Autodesk Fusion 360 part; units mm, degrees
(part 26 of 28)
  line L3064 (63.4347, 75.7056, -1.4859) -> (63.5097, 75.8867, -1.4859)
  line L3065 (63.5097, 75.8867, -1.4859) -> (63.6186, 76.0497, -1.4859)
  line L3066 (63.6186, 76.0497, -1.4859) -> (63.7572, 76.1883, -1.4859)
  line L3067 (63.7572, 76.1883, -1.4859) -> (63.9202, 76.2972, -1.4859)
  line L3068 (63.9202, 76.2972, -1.4859) -> (64.1013, 76.3722, -1.4859)
  line L3069 (64.1013, 76.3722, -1.4859) -> (64.2936, 76.4105, -1.4859)
  line L3070 (64.2936, 76.4105, -1.4859) -> (64.4896, 76.4105, -1.4859)
  line L3071 (64.4896, 76.4105, -1.4859) -> (64.6819, 76.3722, -1.4859)
  line L3072 (96.8769, 76.3722, -1.4859) -> (97.058, 76.2972, -1.4859)
  line L3073 (97.058, 76.2972, -1.4859) -> (97.221, 76.1883, -1.4859)
  line L3074 (97.221, 76.1883, -1.4859) -> (97.3596, 76.0497, -1.4859)
  line L3075 (97.3596, 76.0497, -1.4859) -> (97.4685, 75.8867, -1.4859)
  line L3076 (97.4685, 75.8867, -1.4859) -> (97.5435, 75.7056, -1.4859)
  line L3077 (97.5435, 75.7056, -1.4859) -> (97.5818, 75.5133, -1.4859)
  line L3078 (97.5818, 75.5133, -1.4859) -> (97.5866, 75.4153, -1.4859)
  line L3079 (97.5866, 75.4153, -1.4859) -> (97.5866, 74.2153, -1.4859)
  line L3080 (97.5866, 74.2153, -1.4859) -> (97.5818, 74.1173, -1.4859)
  line L3081 (97.5818, 74.1173, -1.4859) -> (97.5435, 73.925, -1.4859)
  line L3082 (97.5435, 73.925, -1.4859) -> (97.4685, 73.7439, -1.4859)
  line L3083 (97.4685, 73.7439, -1.4859) -> (97.3596, 73.5809, -1.4859)
  line L3084 (97.3596, 73.5809, -1.4859) -> (97.221, 73.4423, -1.4859)
  line L3085 (97.221, 73.4423, -1.4859) -> (97.058, 73.3334, -1.4859)
  line L3086 (97.058, 73.3334, -1.4859) -> (96.8769, 73.2583, -1.4859)
  line L3087 (96.8769, 73.2583, -1.4859) -> (96.6846, 73.2201, -1.4859)
  line L3088 (96.6846, 73.2201, -1.4859) -> (96.4886, 73.2201, -1.4859)
  line L3089 (96.4886, 73.2201, -1.4859) -> (96.2963, 73.2583, -1.4859)
  line L3090 (96.2963, 73.2583, -1.4859) -> (96.1152, 73.3334, -1.4859)
  line L3091 (96.1152, 73.3334, -1.4859) -> (95.9522, 73.4423, -1.4859)
  line L3092 (95.9522, 73.4423, -1.4859) -> (95.8136, 73.5809, -1.4859)
  line L3093 (95.8136, 73.5809, -1.4859) -> (95.7047, 73.7439, -1.4859)
  line L3094 (95.7047, 73.7439, -1.4859) -> (95.6297, 73.925, -1.4859)
  line L3095 (95.6297, 73.925, -1.4859) -> (95.5914, 74.1173, -1.4859)
  line L3096 (95.5914, 74.1173, -1.4859) -> (95.5866, 74.2153, -1.4859)
  line L3097 (95.5866, 74.2153, -1.4859) -> (95.5866, 75.4153, -1.4859)
  line L3098 (95.5866, 75.4153, -1.4859) -> (95.5914, 75.5133, -1.4859)
  line L3099 (95.5914, 75.5133, -1.4859) -> (95.6297, 75.7056, -1.4859)
  line L3100 (95.6297, 75.7056, -1.4859) -> (95.7047, 75.8867, -1.4859)
  line L3101 (95.7047, 75.8867, -1.4859) -> (95.8136, 76.0497, -1.4859)
  line L3102 (95.8136, 76.0497, -1.4859) -> (95.9522, 76.1883, -1.4859)
  line L3103 (95.9522, 76.1883, -1.4859) -> (96.1152, 76.2972, -1.4859)
  line L3104 (96.1152, 76.2972, -1.4859) -> (96.2963, 76.3722, -1.4859)
  line L3105 (96.2963, 76.3722, -1.4859) -> (96.4886, 76.4105, -1.4859)
  line L3106 (96.4886, 76.4105, -1.4859) -> (96.6846, 76.4105, -1.4859)
  line L3107 (96.6846, 76.4105, -1.4859) -> (96.8769, 76.3722, -1.4859)
  line L3108 (99.6069, 76.3722, -1.4859) -> (99.788, 76.2972, -1.4859)
  line L3109 (99.788, 76.2972, -1.4859) -> (99.951, 76.1883, -1.4859)
  line L3110 (99.951, 76.1883, -1.4859) -> (100.0896, 76.0497, -1.4859)
  line L3111 (100.0896, 76.0497, -1.4859) -> (100.1985, 75.8867, -1.4859)
  line L3112 (100.1985, 75.8867, -1.4859) -> (100.2735, 75.7056, -1.4859)
  line L3113 (100.2735, 75.7056, -1.4859) -> (100.3118, 75.5133, -1.4859)
  line L3114 (100.3118, 75.5133, -1.4859) -> (100.3166, 75.4153, -1.4859)
  line L3115 (100.3166, 75.4153, -1.4859) -> (100.3166, 74.2153, -1.4859)
  line L3116 (100.3166, 74.2153, -1.4859) -> (100.3118, 74.1173, -1.4859)
  line L3117 (100.3118, 74.1173, -1.4859) -> (100.2735, 73.925, -1.4859)
  line L3118 (100.2735, 73.925, -1.4859) -> (100.1985, 73.7439, -1.4859)
  line L3119 (100.1985, 73.7439, -1.4859) -> (100.0896, 73.5809, -1.4859)
  line L3120 (100.0896, 73.5809, -1.4859) -> (99.951, 73.4423, -1.4859)
  line L3121 (99.951, 73.4423, -1.4859) -> (99.788, 73.3334, -1.4859)
  line L3122 (99.788, 73.3334, -1.4859) -> (99.6069, 73.2583, -1.4859)
  line L3123 (99.6069, 73.2583, -1.4859) -> (99.4146, 73.2201, -1.4859)
  line L3124 (99.4146, 73.2201, -1.4859) -> (99.2186, 73.2201, -1.4859)
  line L3125 (99.2186, 73.2201, -1.4859) -> (99.0263, 73.2583, -1.4859)
  line L3126 (99.0263, 73.2583, -1.4859) -> (98.8452, 73.3334, -1.4859)
  line L3127 (98.8452, 73.3334, -1.4859) -> (98.6822, 73.4423, -1.4859)
  line L3128 (98.6822, 73.4423, -1.4859) -> (98.5436, 73.5809, -1.4859)
  line L3129 (98.5436, 73.5809, -1.4859) -> (98.4347, 73.7439, -1.4859)
  line L3130 (98.4347, 73.7439, -1.4859) -> (98.3597, 73.925, -1.4859)
  line L3131 (98.3597, 73.925, -1.4859) -> (98.3214, 74.1173, -1.4859)
  line L3132 (98.3214, 74.1173, -1.4859) -> (98.3166, 74.2153, -1.4859)
  line L3133 (98.3166, 74.2153, -1.4859) -> (98.3166, 75.4153, -1.4859)
  line L3134 (98.3166, 75.4153, -1.4859) -> (98.3214, 75.5133, -1.4859)
  line L3135 (98.3214, 75.5133, -1.4859) -> (98.3597, 75.7056, -1.4859)
  line L3136 (98.3597, 75.7056, -1.4859) -> (98.4347, 75.8867, -1.4859)
  line L3137 (98.4347, 75.8867, -1.4859) -> (98.5436, 76.0497, -1.4859)
  line L3138 (98.5436, 76.0497, -1.4859) -> (98.6822, 76.1883, -1.4859)
  line L3139 (98.6822, 76.1883, -1.4859) -> (98.8452, 76.2972, -1.4859)
  line L3140 (98.8452, 76.2972, -1.4859) -> (99.0263, 76.3722, -1.4859)
  line L3141 (99.0263, 76.3722, -1.4859) -> (99.2186, 76.4105, -1.4859)
  line L3142 (99.2186, 76.4105, -1.4859) -> (99.4146, 76.4105, -1.4859)
  line L3143 (99.4146, 76.4105, -1.4859) -> (99.6069, 76.3722, -1.4859)
  line L3144 (131.8019, 76.3722, -1.4859) -> (131.983, 76.2972, -1.4859)
  line L3145 (131.983, 76.2972, -1.4859) -> (132.146, 76.1883, -1.4859)
  line L3146 (132.146, 76.1883, -1.4859) -> (132.2846, 76.0497, -1.4859)
  line L3147 (132.2846, 76.0497, -1.4859) -> (132.3935, 75.8867, -1.4859)
  line L3148 (132.3935, 75.8867, -1.4859) -> (132.4685, 75.7056, -1.4859)
  line L3149 (132.4685, 75.7056, -1.4859) -> (132.5068, 75.5133, -1.4859)
  line L3150 (132.5068, 75.5133, -1.4859) -> (132.5116, 75.4153, -1.4859)
  line L3151 (132.5116, 75.4153, -1.4859) -> (132.5116, 74.2153, -1.4859)
  line L3152 (132.5116, 74.2153, -1.4859) -> (132.5068, 74.1173, -1.4859)
  line L3153 (132.5068, 74.1173, -1.4859) -> (132.4685, 73.925, -1.4859)
  line L3154 (132.4685, 73.925, -1.4859) -> (132.3935, 73.7439, -1.4859)
  line L3155 (132.3935, 73.7439, -1.4859) -> (132.2846, 73.5809, -1.4859)
  line L3156 (132.2846, 73.5809, -1.4859) -> (132.146, 73.4423, -1.4859)
  line L3157 (132.146, 73.4423, -1.4859) -> (131.983, 73.3334, -1.4859)
  line L3158 (131.983, 73.3334, -1.4859) -> (131.8019, 73.2583, -1.4859)
  line L3159 (131.8019, 73.2583, -1.4859) -> (131.6096, 73.2201, -1.4859)
  line L3160 (131.6096, 73.2201, -1.4859) -> (131.4136, 73.2201, -1.4859)
  line L3161 (131.4136, 73.2201, -1.4859) -> (131.2213, 73.2583, -1.4859)
  line L3162 (131.2213, 73.2583, -1.4859) -> (131.0402, 73.3334, -1.4859)
  line L3163 (131.0402, 73.3334, -1.4859) -> (130.8772, 73.4423, -1.4859)
  line L3164 (130.8772, 73.4423, -1.4859) -> (130.7386, 73.5809, -1.4859)
  line L3165 (130.7386, 73.5809, -1.4859) -> (130.6297, 73.7439, -1.4859)
  line L3166 (130.6297, 73.7439, -1.4859) -> (130.5547, 73.925, -1.4859)
  line L3167 (130.5547, 73.925, -1.4859) -> (130.5164, 74.1173, -1.4859)
  line L3168 (130.5164, 74.1173, -1.4859) -> (130.5116, 74.2153, -1.4859)
  line L3169 (130.5116, 74.2153, -1.4859) -> (130.5116, 75.4153, -1.4859)
  line L3170 (130.5116, 75.4153, -1.4859) -> (130.5164, 75.5133, -1.4859)
  line L3171 (130.5164, 75.5133, -1.4859) -> (130.5547, 75.7056, -1.4859)
  line L3172 (130.5547, 75.7056, -1.4859) -> (130.6297, 75.8867, -1.4859)
  line L3173 (130.6297, 75.8867, -1.4859) -> (130.7386, 76.0497, -1.4859)
  line L3174 (130.7386, 76.0497, -1.4859) -> (130.8772, 76.1883, -1.4859)
  line L3175 (130.8772, 76.1883, -1.4859) -> (131.0402, 76.2972, -1.4859)
  line L3176 (131.0402, 76.2972, -1.4859) -> (131.2213, 76.3722, -1.4859)
  line L3177 (131.2213, 76.3722, -1.4859) -> (131.4136, 76.4105, -1.4859)
  line L3178 (131.4136, 76.4105, -1.4859) -> (131.6096, 76.4105, -1.4859)
  line L3179 (131.6096, 76.4105, -1.4859) -> (131.8019, 76.3722, -1.4859)
  line L3180 (134.5319, 76.3722, -1.4859) -> (134.713, 76.2972, -1.4859)
  line L3181 (134.713, 76.2972, -1.4859) -> (134.876, 76.1883, -1.4859)
  line L3182 (134.876, 76.1883, -1.4859) -> (135.0146, 76.0497, -1.4859)
  line L3183 (135.0146, 76.0497, -1.4859) -> (135.1235, 75.8867, -1.4859)
  line L3184 (135.1235, 75.8867, -1.4859) -> (135.1985, 75.7056, -1.4859)
  line L3185 (135.1985, 75.7056, -1.4859) -> (135.2368, 75.5133, -1.4859)
  line L3186 (135.2368, 75.5133, -1.4859) -> (135.2416, 75.4153, -1.4859)
  line L3187 (135.2416, 75.4153, -1.4859) -> (135.2416, 74.2153, -1.4859)
  line L3188 (135.2416, 74.2153, -1.4859) -> (135.2368, 74.1173, -1.4859)
  line L3189 (135.2368, 74.1173, -1.4859) -> (135.1985, 73.925, -1.4859)
  line L3190 (135.1985, 73.925, -1.4859) -> (135.1235, 73.7439, -1.4859)
  line L3191 (135.1235, 73.7439, -1.4859) -> (135.0146, 73.5809, -1.4859)
  line L3192 (135.0146, 73.5809, -1.4859) -> (134.876, 73.4423, -1.4859)
  line L3193 (134.876, 73.4423, -1.4859) -> (134.713, 73.3334, -1.4859)
  line L3194 (134.713, 73.3334, -1.4859) -> (134.5319, 73.2583, -1.4859)
  line L3195 (134.5319, 73.2583, -1.4859) -> (134.3396, 73.2201, -1.4859)
  line L3196 (134.3396, 73.2201, -1.4859) -> (134.1436, 73.2201, -1.4859)
  line L3197 (134.1436, 73.2201, -1.4859) -> (133.9513, 73.2583, -1.4859)
  line L3198 (133.9513, 73.2583, -1.4859) -> (133.7702, 73.3334, -1.4859)
  line L3199 (133.7702, 73.3334, -1.4859) -> (133.6072, 73.4423, -1.4859)
  line L3200 (133.6072, 73.4423, -1.4859) -> (133.4686, 73.5809, -1.4859)
  line L3201 (133.4686, 73.5809, -1.4859) -> (133.3597, 73.7439, -1.4859)
  line L3202 (133.3597, 73.7439, -1.4859) -> (133.2847, 73.925, -1.4859)
  line L3203 (133.2847, 73.925, -1.4859) -> (133.2464, 74.1173, -1.4859)
  line L3204 (133.2464, 74.1173, -1.4859) -> (133.2416, 74.2153, -1.4859)
  line L3205 (133.2416, 74.2153, -1.4859) -> (133.2416, 75.4153, -1.4859)
  line L3206 (133.2416, 75.4153, -1.4859) -> (133.2464, 75.5133, -1.4859)
  line L3207 (133.2464, 75.5133, -1.4859) -> (133.2847, 75.7056, -1.4859)
  line L3208 (133.2847, 75.7056, -1.4859) -> (133.3597, 75.8867, -1.4859)
  line L3209 (133.3597, 75.8867, -1.4859) -> (133.4686, 76.0497, -1.4859)
  line L3210 (133.4686, 76.0497, -1.4859) -> (133.6072, 76.1883, -1.4859)
  line L3211 (133.6072, 76.1883, -1.4859) -> (133.7702, 76.2972, -1.4859)
  line L3212 (133.7702, 76.2972, -1.4859) -> (133.9513, 76.3722, -1.4859)
  line L3213 (133.9513, 76.3722, -1.4859) -> (134.1436, 76.4105, -1.4859)
  line L3214 (134.1436, 76.4105, -1.4859) -> (134.3396, 76.4105, -1.4859)
  line L3215 (134.3396, 76.4105, -1.4859) -> (134.5319, 76.3722, -1.4859)
  line L3216 (14.4315, 73.2735, -1.4859) -> (12.4315, 73.2735, -1.4859)
  line L3217 (12.4315, 73.2735, -1.4859) -> (12.4315, 76.4735, -1.4859)
  line L3218 (12.4315, 76.4735, -1.4859) -> (14.4315, 76.4735, -1.4859)
  line L3219 (14.4315, 76.4735, -1.4859) -> (14.4315, 73.2735, -1.4859)
  line L3220 (49.3565, 73.2735, -1.4859) -> (47.3565, 73.2735, -1.4859)
  line L3221 (47.3565, 73.2735, -1.4859) -> (47.3565, 76.4735, -1.4859)
  line L3222 (47.3565, 76.4735, -1.4859) -> (49.3565, 76.4735, -1.4859)
  line L3223 (49.3565, 76.4735, -1.4859) -> (49.3565, 73.2735, -1.4859)
  line L3224 (84.2815, 73.2735, -1.4859) -> (82.2815, 73.2735, -1.4859)
  line L3225 (82.2815, 73.2735, -1.4859) -> (82.2815, 76.4735, -1.4859)
  line L3226 (82.2815, 76.4735, -1.4859) -> (84.2815, 76.4735, -1.4859)
  line L3227 (84.2815, 76.4735, -1.4859) -> (84.2815, 73.2735, -1.4859)
  line L3228 (119.2065, 73.2735, -1.4859) -> (117.2065, 73.2735, -1.4859)
  line L3229 (117.2065, 73.2735, -1.4859) -> (117.2065, 76.4735, -1.4859)
  line L3230 (117.2065, 76.4735, -1.4859) -> (119.2065, 76.4735, -1.4859)
  line L3231 (119.2065, 76.4735, -1.4859) -> (119.2065, 73.2735, -1.4859)
  line L3232 (16.4918, 76.4304, -1.4859) -> (16.6729, 76.3554, -1.4859)
  line L3233 (16.6729, 76.3554, -1.4859) -> (16.8359, 76.2465, -1.4859)
  line L3234 (16.8359, 76.2465, -1.4859) -> (16.9745, 76.1079, -1.4859)
  line L3235 (16.9745, 76.1079, -1.4859) -> (17.0834, 75.9449, -1.4859)
  line L3236 (17.0834, 75.9449, -1.4859) -> (17.1585, 75.7638, -1.4859)
  line L3237 (17.1585, 75.7638, -1.4859) -> (17.1967, 75.5715, -1.4859)
  line L3238 (17.1967, 75.5715, -1.4859) -> (17.2015, 75.4735, -1.4859)
  line L3239 (17.2015, 75.4735, -1.4859) -> (17.2015, 74.2735, -1.4859)
  line L3240 (17.2015, 74.2735, -1.4859) -> (17.1967, 74.1755, -1.4859)
  line L3241 (17.1967, 74.1755, -1.4859) -> (17.1585, 73.9832, -1.4859)
  line L3242 (17.1585, 73.9832, -1.4859) -> (17.0834, 73.8021, -1.4859)
  line L3243 (17.0834, 73.8021, -1.4859) -> (16.9745, 73.6391, -1.4859)
  line L3244 (16.9745, 73.6391, -1.4859) -> (16.8359, 73.5005, -1.4859)
  line L3245 (16.8359, 73.5005, -1.4859) -> (16.6729, 73.3916, -1.4859)
  line L3246 (16.6729, 73.3916, -1.4859) -> (16.4918, 73.3165, -1.4859)
  line L3247 (16.4918, 73.3165, -1.4859) -> (16.2995, 73.2783, -1.4859)
  line L3248 (16.2995, 73.2783, -1.4859) -> (16.1035, 73.2783, -1.4859)
  line L3249 (16.1035, 73.2783, -1.4859) -> (15.9112, 73.3165, -1.4859)
  line L3250 (15.9112, 73.3165, -1.4859) -> (15.7301, 73.3916, -1.4859)
  line L3251 (15.7301, 73.3916, -1.4859) -> (15.5671, 73.5005, -1.4859)
  line L3252 (15.5671, 73.5005, -1.4859) -> (15.4285, 73.6391, -1.4859)
  line L3253 (15.4285, 73.6391, -1.4859) -> (15.3196, 73.8021, -1.4859)
  line L3254 (15.3196, 73.8021, -1.4859) -> (15.2446, 73.9832, -1.4859)
  line L3255 (15.2446, 73.9832, -1.4859) -> (15.2063, 74.1755, -1.4859)
  line L3256 (15.2063, 74.1755, -1.4859) -> (15.2015, 74.2735, -1.4859)
  line L3257 (15.2015, 74.2735, -1.4859) -> (15.2015, 75.4735, -1.4859)
  line L3258 (15.2015, 75.4735, -1.4859) -> (15.2063, 75.5715, -1.4859)
  line L3259 (15.2063, 75.5715, -1.4859) -> (15.2446, 75.7638, -1.4859)
  line L3260 (15.2446, 75.7638, -1.4859) -> (15.3196, 75.9449, -1.4859)
  line L3261 (15.3196, 75.9449, -1.4859) -> (15.4285, 76.1079, -1.4859)
  line L3262 (15.4285, 76.1079, -1.4859) -> (15.5671, 76.2465, -1.4859)
  line L3263 (15.5671, 76.2465, -1.4859) -> (15.7301, 76.3554, -1.4859)
  line L3264 (15.7301, 76.3554, -1.4859) -> (15.9112, 76.4304, -1.4859)
  line L3265 (15.9112, 76.4304, -1.4859) -> (16.1035, 76.4687, -1.4859)
  line L3266 (16.1035, 76.4687, -1.4859) -> (16.2995, 76.4687, -1.4859)
  line L3267 (16.2995, 76.4687, -1.4859) -> (16.4918, 76.4304, -1.4859)
  line L3268 (19.2218, 76.4304, -1.4859) -> (19.4029, 76.3554, -1.4859)
  line L3269 (19.4029, 76.3554, -1.4859) -> (19.5659, 76.2465, -1.4859)
  line L3270 (19.5659, 76.2465, -1.4859) -> (19.7045, 76.1079, -1.4859)
  line L3271 (19.7045, 76.1079, -1.4859) -> (19.8134, 75.9449, -1.4859)
  line L3272 (19.8134, 75.9449, -1.4859) -> (19.8885, 75.7638, -1.4859)
  line L3273 (19.8885, 75.7638, -1.4859) -> (19.9267, 75.5715, -1.4859)
  line L3274 (19.9267, 75.5715, -1.4859) -> (19.9315, 75.4735, -1.4859)
  line L3275 (19.9315, 75.4735, -1.4859) -> (19.9315, 74.2735, -1.4859)
  line L3276 (19.9315, 74.2735, -1.4859) -> (19.9267, 74.1755, -1.4859)
  line L3277 (19.9267, 74.1755, -1.4859) -> (19.8885, 73.9832, -1.4859)
  line L3278 (19.8885, 73.9832, -1.4859) -> (19.8134, 73.8021, -1.4859)
  line L3279 (19.8134, 73.8021, -1.4859) -> (19.7045, 73.6391, -1.4859)
  line L3280 (19.7045, 73.6391, -1.4859) -> (19.5659, 73.5005, -1.4859)
  line L3281 (19.5659, 73.5005, -1.4859) -> (19.4029, 73.3916, -1.4859)
  line L3282 (19.4029, 73.3916, -1.4859) -> (19.2218, 73.3165, -1.4859)
  line L3283 (19.2218, 73.3165, -1.4859) -> (19.0295, 73.2783, -1.4859)
  line L3284 (19.0295, 73.2783, -1.4859) -> (18.8335, 73.2783, -1.4859)
  line L3285 (18.8335, 73.2783, -1.4859) -> (18.6412, 73.3165, -1.4859)
  line L3286 (18.6412, 73.3165, -1.4859) -> (18.4601, 73.3916, -1.4859)
  line L3287 (18.4601, 73.3916, -1.4859) -> (18.2971, 73.5005, -1.4859)
  line L3288 (18.2971, 73.5005, -1.4859) -> (18.1585, 73.6391, -1.4859)
  line L3289 (18.1585, 73.6391, -1.4859) -> (18.0496, 73.8021, -1.4859)
  line L3290 (18.0496, 73.8021, -1.4859) -> (17.9746, 73.9832, -1.4859)
  line L3291 (17.9746, 73.9832, -1.4859) -> (17.9363, 74.1755, -1.4859)
  line L3292 (17.9363, 74.1755, -1.4859) -> (17.9315, 74.2735, -1.4859)
  line L3293 (17.9315, 74.2735, -1.4859) -> (17.9315, 75.4735, -1.4859)
  line L3294 (17.9315, 75.4735, -1.4859) -> (17.9363, 75.5715, -1.4859)
  line L3295 (17.9363, 75.5715, -1.4859) -> (17.9746, 75.7638, -1.4859)
  line L3296 (17.9746, 75.7638, -1.4859) -> (18.0496, 75.9449, -1.4859)
  line L3297 (18.0496, 75.9449, -1.4859) -> (18.1585, 76.1079, -1.4859)
  line L3298 (18.1585, 76.1079, -1.4859) -> (18.2971, 76.2465, -1.4859)
  line L3299 (18.2971, 76.2465, -1.4859) -> (18.4601, 76.3554, -1.4859)
  line L3300 (18.4601, 76.3554, -1.4859) -> (18.6412, 76.4304, -1.4859)
  line L3301 (18.6412, 76.4304, -1.4859) -> (18.8335, 76.4687, -1.4859)
  line L3302 (18.8335, 76.4687, -1.4859) -> (19.0295, 76.4687, -1.4859)
  line L3303 (19.0295, 76.4687, -1.4859) -> (19.2218, 76.4304, -1.4859)
  line L3304 (51.4168, 76.4304, -1.4859) -> (51.5979, 76.3554, -1.4859)
  line L3305 (51.5979, 76.3554, -1.4859) -> (51.7609, 76.2465, -1.4859)
  line L3306 (51.7609, 76.2465, -1.4859) -> (51.8995, 76.1079, -1.4859)
  line L3307 (51.8995, 76.1079, -1.4859) -> (52.0084, 75.9449, -1.4859)
  line L3308 (52.0084, 75.9449, -1.4859) -> (52.0835, 75.7638, -1.4859)
  line L3309 (52.0835, 75.7638, -1.4859) -> (52.1217, 75.5715, -1.4859)
  line L3310 (52.1217, 75.5715, -1.4859) -> (52.1265, 75.4735, -1.4859)
  line L3311 (52.1265, 75.4735, -1.4859) -> (52.1265, 74.2735, -1.4859)
  line L3312 (52.1265, 74.2735, -1.4859) -> (52.1217, 74.1755, -1.4859)
  line L3313 (52.1217, 74.1755, -1.4859) -> (52.0835, 73.9832, -1.4859)
  line L3314 (52.0835, 73.9832, -1.4859) -> (52.0084, 73.8021, -1.4859)
  line L3315 (52.0084, 73.8021, -1.4859) -> (51.8995, 73.6391, -1.4859)
  line L3316 (51.8995, 73.6391, -1.4859) -> (51.7609, 73.5005, -1.4859)
  line L3317 (51.7609, 73.5005, -1.4859) -> (51.5979, 73.3916, -1.4859)
  line L3318 (51.5979, 73.3916, -1.4859) -> (51.4168, 73.3165, -1.4859)
  line L3319 (51.4168, 73.3165, -1.4859) -> (51.2245, 73.2783, -1.4859)
  line L3320 (51.2245, 73.2783, -1.4859) -> (51.0285, 73.2783, -1.4859)
  line L3321 (51.0285, 73.2783, -1.4859) -> (50.8362, 73.3165, -1.4859)
  line L3322 (50.8362, 73.3165, -1.4859) -> (50.6551, 73.3916, -1.4859)
  line L3323 (50.6551, 73.3916, -1.4859) -> (50.4921, 73.5005, -1.4859)
  line L3324 (50.4921, 73.5005, -1.4859) -> (50.3535, 73.6391, -1.4859)
  line L3325 (50.3535, 73.6391, -1.4859) -> (50.2446, 73.8021, -1.4859)
  line L3326 (50.2446, 73.8021, -1.4859) -> (50.1696, 73.9832, -1.4859)
  line L3327 (50.1696, 73.9832, -1.4859) -> (50.1313, 74.1755, -1.4859)
  line L3328 (50.1313, 74.1755, -1.4859) -> (50.1265, 74.2735, -1.4859)
  line L3329 (50.1265, 74.2735, -1.4859) -> (50.1265, 75.4735, -1.4859)
  line L3330 (50.1265, 75.4735, -1.4859) -> (50.1313, 75.5715, -1.4859)
  line L3331 (50.1313, 75.5715, -1.4859) -> (50.1696, 75.7638, -1.4859)
  line L3332 (50.1696, 75.7638, -1.4859) -> (50.2446, 75.9449, -1.4859)
  line L3333 (50.2446, 75.9449, -1.4859) -> (50.3535, 76.1079, -1.4859)
  line L3334 (50.3535, 76.1079, -1.4859) -> (50.4921, 76.2465, -1.4859)
  line L3335 (50.4921, 76.2465, -1.4859) -> (50.6551, 76.3554, -1.4859)
  line L3336 (50.6551, 76.3554, -1.4859) -> (50.8362, 76.4304, -1.4859)
  line L3337 (50.8362, 76.4304, -1.4859) -> (51.0285, 76.4687, -1.4859)
  line L3338 (51.0285, 76.4687, -1.4859) -> (51.2245, 76.4687, -1.4859)
  line L3339 (51.2245, 76.4687, -1.4859) -> (51.4168, 76.4304, -1.4859)
  line L3340 (54.1468, 76.4304, -1.4859) -> (54.3279, 76.3554, -1.4859)
  line L3341 (54.3279, 76.3554, -1.4859) -> (54.4909, 76.2465, -1.4859)
  line L3342 (54.4909, 76.2465, -1.4859) -> (54.6295, 76.1079, -1.4859)
  line L3343 (54.6295, 76.1079, -1.4859) -> (54.7384, 75.9449, -1.4859)
  line L3344 (54.7384, 75.9449, -1.4859) -> (54.8135, 75.7638, -1.4859)
  line L3345 (54.8135, 75.7638, -1.4859) -> (54.8517, 75.5715, -1.4859)
  line L3346 (54.8517, 75.5715, -1.4859) -> (54.8565, 75.4735, -1.4859)
  line L3347 (54.8565, 75.4735, -1.4859) -> (54.8565, 74.2735, -1.4859)
  line L3348 (54.8565, 74.2735, -1.4859) -> (54.8517, 74.1755, -1.4859)
  line L3349 (54.8517, 74.1755, -1.4859) -> (54.8135, 73.9832, -1.4859)
  line L3350 (54.8135, 73.9832, -1.4859) -> (54.7384, 73.8021, -1.4859)
  line L3351 (54.7384, 73.8021, -1.4859) -> (54.6295, 73.6391, -1.4859)
  line L3352 (54.6295, 73.6391, -1.4859) -> (54.4909, 73.5005, -1.4859)
  line L3353 (54.4909, 73.5005, -1.4859) -> (54.3279, 73.3916, -1.4859)
  line L3354 (54.3279, 73.3916, -1.4859) -> (54.1468, 73.3165, -1.4859)
  line L3355 (54.1468, 73.3165, -1.4859) -> (53.9545, 73.2783, -1.4859)
  line L3356 (53.9545, 73.2783, -1.4859) -> (53.7585, 73.2783, -1.4859)
  line L3357 (53.7585, 73.2783, -1.4859) -> (53.5662, 73.3165, -1.4859)
  line L3358 (53.5662, 73.3165, -1.4859) -> (53.3851, 73.3916, -1.4859)
  line L3359 (53.3851, 73.3916, -1.4859) -> (53.2221, 73.5005, -1.4859)
  line L3360 (53.2221, 73.5005, -1.4859) -> (53.0835, 73.6391, -1.4859)
  line L3361 (53.0835, 73.6391, -1.4859) -> (52.9746, 73.8021, -1.4859)
  line L3362 (52.9746, 73.8021, -1.4859) -> (52.8996, 73.9832, -1.4859)
  line L3363 (52.8996, 73.9832, -1.4859) -> (52.8613, 74.1755, -1.4859)
  line L3364 (52.8613, 74.1755, -1.4859) -> (52.8565, 74.2735, -1.4859)
  line L3365 (52.8565, 74.2735, -1.4859) -> (52.8565, 75.4735, -1.4859)
  line L3366 (52.8565, 75.4735, -1.4859) -> (52.8613, 75.5715, -1.4859)
  line L3367 (52.8613, 75.5715, -1.4859) -> (52.8996, 75.7638, -1.4859)
  line L3368 (52.8996, 75.7638, -1.4859) -> (52.9746, 75.9449, -1.4859)
  line L3369 (52.9746, 75.9449, -1.4859) -> (53.0835, 76.1079, -1.4859)
  line L3370 (53.0835, 76.1079, -1.4859) -> (53.2221, 76.2465, -1.4859)
  line L3371 (53.2221, 76.2465, -1.4859) -> (53.3851, 76.3554, -1.4859)
  line L3372 (53.3851, 76.3554, -1.4859) -> (53.5662, 76.4304, -1.4859)
  line L3373 (53.5662, 76.4304, -1.4859) -> (53.7585, 76.4687, -1.4859)
  line L3374 (53.7585, 76.4687, -1.4859) -> (53.9545, 76.4687, -1.4859)
  line L3375 (53.9545, 76.4687, -1.4859) -> (54.1468, 76.4304, -1.4859)
  line L3376 (86.3418, 76.4304, -1.4859) -> (86.5229, 76.3554, -1.4859)
  line L3377 (86.5229, 76.3554, -1.4859) -> (86.6859, 76.2465, -1.4859)
  line L3378 (86.6859, 76.2465, -1.4859) -> (86.8245, 76.1079, -1.4859)
  line L3379 (86.8245, 76.1079, -1.4859) -> (86.9334, 75.9449, -1.4859)
  line L3380 (86.9334, 75.9449, -1.4859) -> (87.0085, 75.7638, -1.4859)
  line L3381 (87.0085, 75.7638, -1.4859) -> (87.0467, 75.5715, -1.4859)
  line L3382 (87.0467, 75.5715, -1.4859) -> (87.0515, 75.4735, -1.4859)
  line L3383 (87.0515, 75.4735, -1.4859) -> (87.0515, 74.2735, -1.4859)
  line L3384 (87.0515, 74.2735, -1.4859) -> (87.0467, 74.1755, -1.4859)
  line L3385 (87.0467, 74.1755, -1.4859) -> (87.0085, 73.9832, -1.4859)
  line L3386 (87.0085, 73.9832, -1.4859) -> (86.9334, 73.8021, -1.4859)
  line L3387 (86.9334, 73.8021, -1.4859) -> (86.8245, 73.6391, -1.4859)
  line L3388 (86.8245, 73.6391, -1.4859) -> (86.6859, 73.5005, -1.4859)
  line L3389 (86.6859, 73.5005, -1.4859) -> (86.5229, 73.3916, -1.4859)
  line L3390 (86.5229, 73.3916, -1.4859) -> (86.3418, 73.3165, -1.4859)
  line L3391 (86.3418, 73.3165, -1.4859) -> (86.1495, 73.2783, -1.4859)
  line L3392 (86.1495, 73.2783, -1.4859) -> (85.9535, 73.2783, -1.4859)
  line L3393 (85.9535, 73.2783, -1.4859) -> (85.7612, 73.3165, -1.4859)
  line L3394 (85.7612, 73.3165, -1.4859) -> (85.5801, 73.3916, -1.4859)
  line L3395 (85.5801, 73.3916, -1.4859) -> (85.4171, 73.5005, -1.4859)
  line L3396 (85.4171, 73.5005, -1.4859) -> (85.2785, 73.6391, -1.4859)
  line L3397 (85.2785, 73.6391, -1.4859) -> (85.1696, 73.8021, -1.4859)
  line L3398 (85.1696, 73.8021, -1.4859) -> (85.0946, 73.9832, -1.4859)
  line L3399 (85.0946, 73.9832, -1.4859) -> (85.0563, 74.1755, -1.4859)
  line L3400 (85.0563, 74.1755, -1.4859) -> (85.0515, 74.2735, -1.4859)
  line L3401 (85.0515, 74.2735, -1.4859) -> (85.0515, 75.4735, -1.4859)
  line L3402 (85.0515, 75.4735, -1.4859) -> (85.0563, 75.5715, -1.4859)
  line L3403 (85.0563, 75.5715, -1.4859) -> (85.0946, 75.7638, -1.4859)
  line L3404 (85.0946, 75.7638, -1.4859) -> (85.1696, 75.9449, -1.4859)
  line L3405 (85.1696, 75.9449, -1.4859) -> (85.2785, 76.1079, -1.4859)
  line L3406 (85.2785, 76.1079, -1.4859) -> (85.4171, 76.2465, -1.4859)
  line L3407 (85.4171, 76.2465, -1.4859) -> (85.5801, 76.3554, -1.4859)
  line L3408 (85.5801, 76.3554, -1.4859) -> (85.7612, 76.4304, -1.4859)
  line L3409 (85.7612, 76.4304, -1.4859) -> (85.9535, 76.4687, -1.4859)
  line L3410 (85.9535, 76.4687, -1.4859) -> (86.1495, 76.4687, -1.4859)
  line L3411 (86.1495, 76.4687, -1.4859) -> (86.3418, 76.4304, -1.4859)
  line L3412 (89.0718, 76.4304, -1.4859) -> (89.2529, 76.3554, -1.4859)
  line L3413 (89.2529, 76.3554, -1.4859) -> (89.4159, 76.2465, -1.4859)
  line L3414 (89.4159, 76.2465, -1.4859) -> (89.5545, 76.1079, -1.4859)
  line L3415 (89.5545, 76.1079, -1.4859) -> (89.6634, 75.9449, -1.4859)
  line L3416 (89.6634, 75.9449, -1.4859) -> (89.7385, 75.7638, -1.4859)
  line L3417 (89.7385, 75.7638, -1.4859) -> (89.7767, 75.5715, -1.4859)
  line L3418 (89.7767, 75.5715, -1.4859) -> (89.7815, 75.4735, -1.4859)
  line L3419 (89.7815, 75.4735, -1.4859) -> (89.7815, 74.2735, -1.4859)
  line L3420 (89.7815, 74.2735, -1.4859) -> (89.7767, 74.1755, -1.4859)
  line L3421 (89.7767, 74.1755, -1.4859) -> (89.7385, 73.9832, -1.4859)
  line L3422 (89.7385, 73.9832, -1.4859) -> (89.6634, 73.8021, -1.4859)
  line L3423 (89.6634, 73.8021, -1.4859) -> (89.5545, 73.6391, -1.4859)
  line L3424 (89.5545, 73.6391, -1.4859) -> (89.4159, 73.5005, -1.4859)
  line L3425 (89.4159, 73.5005, -1.4859) -> (89.2529, 73.3916, -1.4859)
  line L3426 (89.2529, 73.3916, -1.4859) -> (89.0718, 73.3165, -1.4859)
  line L3427 (89.0718, 73.3165, -1.4859) -> (88.8795, 73.2783, -1.4859)
  line L3428 (88.8795, 73.2783, -1.4859) -> (88.6835, 73.2783, -1.4859)
  line L3429 (88.6835, 73.2783, -1.4859) -> (88.4912, 73.3165, -1.4859)
  line L3430 (88.4912, 73.3165, -1.4859) -> (88.3101, 73.3916, -1.4859)
  line L3431 (88.3101, 73.3916, -1.4859) -> (88.1471, 73.5005, -1.4859)
  line L3432 (88.1471, 73.5005, -1.4859) -> (88.0085, 73.6391, -1.4859)
  line L3433 (88.0085, 73.6391, -1.4859) -> (87.8996, 73.8021, -1.4859)
  line L3434 (87.8996, 73.8021, -1.4859) -> (87.8246, 73.9832, -1.4859)
  line L3435 (87.8246, 73.9832, -1.4859) -> (87.7863, 74.1755, -1.4859)
  line L3436 (87.7863, 74.1755, -1.4859) -> (87.7815, 74.2735, -1.4859)
  line L3437 (87.7815, 74.2735, -1.4859) -> (87.7815, 75.4735, -1.4859)
  line L3438 (87.7815, 75.4735, -1.4859) -> (87.7863, 75.5715, -1.4859)
  line L3439 (87.7863, 75.5715, -1.4859) -> (87.8246, 75.7638, -1.4859)
  line L3440 (87.8246, 75.7638, -1.4859) -> (87.8996, 75.9449, -1.4859)
  line L3441 (87.8996, 75.9449, -1.4859) -> (88.0085, 76.1079, -1.4859)
  line L3442 (88.0085, 76.1079, -1.4859) -> (88.1471, 76.2465, -1.4859)
  line L3443 (88.1471, 76.2465, -1.4859) -> (88.3101, 76.3554, -1.4859)
  line L3444 (88.3101, 76.3554, -1.4859) -> (88.4912, 76.4304, -1.4859)
  line L3445 (88.4912, 76.4304, -1.4859) -> (88.6835, 76.4687, -1.4859)
  line L3446 (88.6835, 76.4687, -1.4859) -> (88.8795, 76.4687, -1.4859)
  line L3447 (88.8795, 76.4687, -1.4859) -> (89.0718, 76.4304, -1.4859)
  line L3448 (121.2668, 76.4304, -1.4859) -> (121.4479, 76.3554, -1.4859)
  line L3449 (121.4479, 76.3554, -1.4859) -> (121.6109, 76.2465, -1.4859)
  line L3450 (121.6109, 76.2465, -1.4859) -> (121.7495, 76.1079, -1.4859)
  line L3451 (121.7495, 76.1079, -1.4859) -> (121.8584, 75.9449, -1.4859)
  line L3452 (121.8584, 75.9449, -1.4859) -> (121.9335, 75.7638, -1.4859)
  line L3453 (121.9335, 75.7638, -1.4859) -> (121.9717, 75.5715, -1.4859)
  line L3454 (121.9717, 75.5715, -1.4859) -> (121.9765, 75.4735, -1.4859)
  line L3455 (121.9765, 75.4735, -1.4859) -> (121.9765, 74.2735, -1.4859)
  line L3456 (121.9765, 74.2735, -1.4859) -> (121.9717, 74.1755, -1.4859)
  line L3457 (121.9717, 74.1755, -1.4859) -> (121.9335, 73.9832, -1.4859)
  line L3458 (121.9335, 73.9832, -1.4859) -> (121.8584, 73.8021, -1.4859)
  line L3459 (121.8584, 73.8021, -1.4859) -> (121.7495, 73.6391, -1.4859)
  line L3460 (121.7495, 73.6391, -1.4859) -> (121.6109, 73.5005, -1.4859)
  line L3461 (121.6109, 73.5005, -1.4859) -> (121.4479, 73.3916, -1.4859)
  line L3462 (121.4479, 73.3916, -1.4859) -> (121.2668, 73.3165, -1.4859)
  line L3463 (121.2668, 73.3165, -1.4859) -> (121.0745, 73.2783, -1.4859)
  line L3464 (121.0745, 73.2783, -1.4859) -> (120.8785, 73.2783, -1.4859)
  line L3465 (120.8785, 73.2783, -1.4859) -> (120.6862, 73.3165, -1.4859)
  line L3466 (120.6862, 73.3165, -1.4859) -> (120.5051, 73.3916, -1.4859)
  line L3467 (120.5051, 73.3916, -1.4859) -> (120.3421, 73.5005, -1.4859)
  line L3468 (120.3421, 73.5005, -1.4859) -> (120.2035, 73.6391, -1.4859)
  line L3469 (120.2035, 73.6391, -1.4859) -> (120.0946, 73.8021, -1.4859)
  line L3470 (120.0946, 73.8021, -1.4859) -> (120.0196, 73.9832, -1.4859)
  line L3471 (120.0196, 73.9832, -1.4859) -> (119.9813, 74.1755, -1.4859)
  line L3472 (119.9813, 74.1755, -1.4859) -> (119.9765, 74.2735, -1.4859)
  line L3473 (119.9765, 74.2735, -1.4859) -> (119.9765, 75.4735, -1.4859)
  line L3474 (119.9765, 75.4735, -1.4859) -> (119.9813, 75.5715, -1.4859)
  line L3475 (119.9813, 75.5715, -1.4859) -> (120.0196, 75.7638, -1.4859)
  line L3476 (120.0196, 75.7638, -1.4859) -> (120.0946, 75.9449, -1.4859)
  line L3477 (120.0946, 75.9449, -1.4859) -> (120.2035, 76.1079, -1.4859)
  line L3478 (120.2035, 76.1079, -1.4859) -> (120.3421, 76.2465, -1.4859)
  line L3479 (120.3421, 76.2465, -1.4859) -> (120.5051, 76.3554, -1.4859)
  line L3480 (120.5051, 76.3554, -1.4859) -> (120.6862, 76.4304, -1.4859)
  line L3481 (120.6862, 76.4304, -1.4859) -> (120.8785, 76.4687, -1.4859)
  line L3482 (120.8785, 76.4687, -1.4859) -> (121.0745, 76.4687, -1.4859)
  line L3483 (121.0745, 76.4687, -1.4859) -> (121.2668, 76.4304, -1.4859)
  line L3484 (123.9968, 76.4304, -1.4859) -> (124.1779, 76.3554, -1.4859)
  line L3485 (124.1779, 76.3554, -1.4859) -> (124.3409, 76.2465, -1.4859)
  line L3486 (124.3409, 76.2465, -1.4859) -> (124.4795, 76.1079, -1.4859)
  line L3487 (124.4795, 76.1079, -1.4859) -> (124.5884, 75.9449, -1.4859)
  line L3488 (124.5884, 75.9449, -1.4859) -> (124.6635, 75.7638, -1.4859)
  line L3489 (124.6635, 75.7638, -1.4859) -> (124.7017, 75.5715, -1.4859)
  line L3490 (124.7017, 75.5715, -1.4859) -> (124.7065, 75.4735, -1.4859)
  line L3491 (124.7065, 75.4735, -1.4859) -> (124.7065, 74.2735, -1.4859)
  line L3492 (124.7065, 74.2735, -1.4859) -> (124.7017, 74.1755, -1.4859)
  line L3493 (124.7017, 74.1755, -1.4859) -> (124.6635, 73.9832, -1.4859)
  line L3494 (124.6635, 73.9832, -1.4859) -> (124.5884, 73.8021, -1.4859)
  line L3495 (124.5884, 73.8021, -1.4859) -> (124.4795, 73.6391, -1.4859)
  line L3496 (124.4795, 73.6391, -1.4859) -> (124.3409, 73.5005, -1.4859)
  line L3497 (124.3409, 73.5005, -1.4859) -> (124.1779, 73.3916, -1.4859)
  line L3498 (124.1779, 73.3916, -1.4859) -> (123.9968, 73.3165, -1.4859)
  line L3499 (123.9968, 73.3165, -1.4859) -> (123.8045, 73.2783, -1.4859)
  line L3500 (123.8045, 73.2783, -1.4859) -> (123.6085, 73.2783, -1.4859)
  line L3501 (123.6085, 73.2783, -1.4859) -> (123.4162, 73.3165, -1.4859)
  line L3502 (123.4162, 73.3165, -1.4859) -> (123.2351, 73.3916, -1.4859)
  line L3503 (123.2351, 73.3916, -1.4859) -> (123.0721, 73.5005, -1.4859)
  line L3504 (123.0721, 73.5005, -1.4859) -> (122.9335, 73.6391, -1.4859)
  line L3505 (122.9335, 73.6391, -1.4859) -> (122.8246, 73.8021, -1.4859)
  line L3506 (122.8246, 73.8021, -1.4859) -> (122.7496, 73.9832, -1.4859)
  line L3507 (122.7496, 73.9832, -1.4859) -> (122.7113, 74.1755, -1.4859)
  line L3508 (122.7113, 74.1755, -1.4859) -> (122.7065, 74.2735, -1.4859)
  line L3509 (122.7065, 74.2735, -1.4859) -> (122.7065, 75.4735, -1.4859)
  line L3510 (122.7065, 75.4735, -1.4859) -> (122.7113, 75.5715, -1.4859)
  line L3511 (122.7113, 75.5715, -1.4859) -> (122.7496, 75.7638, -1.4859)
  line L3512 (122.7496, 75.7638, -1.4859) -> (122.8246, 75.9449, -1.4859)
  line L3513 (122.8246, 75.9449, -1.4859) -> (122.9335, 76.1079, -1.4859)
  line L3514 (122.9335, 76.1079, -1.4859) -> (123.0721, 76.2465, -1.4859)
  line L3515 (123.0721, 76.2465, -1.4859) -> (123.2351, 76.3554, -1.4859)
  line L3516 (123.2351, 76.3554, -1.4859) -> (123.4162, 76.4304, -1.4859)
  line L3517 (123.4162, 76.4304, -1.4859) -> (123.6085, 76.4687, -1.4859)
  line L3518 (123.6085, 76.4687, -1.4859) -> (123.8045, 76.4687, -1.4859)
  line L3519 (123.8045, 76.4687, -1.4859) -> (123.9968, 76.4304, -1.4859)
  line L3520 (14.5173, 82.8132, -1.4859) -> (14.711, 82.7825, -1.4859)
  line L3521 (14.711, 82.7825, -1.4859) -> (14.8975, 82.7219, -1.4859)
  line L3522 (14.8975, 82.7219, -1.4859) -> (15.0723, 82.6328, -1.4859)
  line L3523 (15.0723, 82.6328, -1.4859) -> (15.231, 82.5175, -1.4859)
  line L3524 (15.231, 82.5175, -1.4859) -> (15.3697, 82.3788, -1.4859)
  line L3525 (15.3697, 82.3788, -1.4859) -> (15.485, 82.2202, -1.4859)
  line L3526 (15.485, 82.2202, -1.4859) -> (15.574, 82.0454, -1.4859)
  line L3527 (15.574, 82.0454, -1.4859) -> (15.6346, 81.8588, -1.4859)
  line L3528 (15.6346, 81.8588, -1.4859) -> (15.6653, 81.6651, -1.4859)
  line L3529 (15.6653, 81.6651, -1.4859) -> (15.6653, 81.469, -1.4859)
  line L3530 (15.6653, 81.469, -1.4859) -> (15.6346, 81.2752, -1.4859)
  line L3531 (15.6346, 81.2752, -1.4859) -> (15.574, 81.0887, -1.4859)
  line L3532 (15.574, 81.0887, -1.4859) -> (15.485, 80.9139, -1.4859)
  line L3533 (15.485, 80.9139, -1.4859) -> (15.3697, 80.7552, -1.4859)
  line L3534 (15.3697, 80.7552, -1.4859) -> (15.231, 80.6165, -1.4859)
  line L3535 (15.231, 80.6165, -1.4859) -> (15.0723, 80.5012, -1.4859)
  line L3536 (15.0723, 80.5012, -1.4859) -> (14.8975, 80.4122, -1.4859)
  line L3537 (14.8975, 80.4122, -1.4859) -> (14.711, 80.3516, -1.4859)
  line L3538 (14.711, 80.3516, -1.4859) -> (14.5173, 80.3209, -1.4859)
  line L3539 (14.5173, 80.3209, -1.4859) -> (14.4192, 80.317, -1.4859)
  line L3540 (14.4192, 80.317, -1.4859) -> (13.9192, 80.317, -1.4859)
  line L3541 (13.9192, 80.317, -1.4859) -> (13.8211, 80.3209, -1.4859)
  line L3542 (13.8211, 80.3209, -1.4859) -> (13.6274, 80.3516, -1.4859)
  line L3543 (13.6274, 80.3516, -1.4859) -> (13.4408, 80.4122, -1.4859)
  line L3544 (13.4408, 80.4122, -1.4859) -> (13.2661, 80.5012, -1.4859)
  line L3545 (13.2661, 80.5012, -1.4859) -> (13.1074, 80.6165, -1.4859)
  line L3546 (13.1074, 80.6165, -1.4859) -> (12.9687, 80.7552, -1.4859)
  line L3547 (12.9687, 80.7552, -1.4859) -> (12.8534, 80.9139, -1.4859)
  line L3548 (12.8534, 80.9139, -1.4859) -> (12.7643, 81.0887, -1.4859)
  line L3549 (12.7643, 81.0887, -1.4859) -> (12.7037, 81.2752, -1.4859)
  line L3550 (12.7037, 81.2752, -1.4859) -> (12.673, 81.469, -1.4859)
  line L3551 (12.673, 81.469, -1.4859) -> (12.673, 81.6651, -1.4859)
  line L3552 (12.673, 81.6651, -1.4859) -> (12.7037, 81.8588, -1.4859)
  line L3553 (12.7037, 81.8588, -1.4859) -> (12.7643, 82.0454, -1.4859)
  line L3554 (12.7643, 82.0454, -1.4859) -> (12.8534, 82.2202, -1.4859)
  line L3555 (12.8534, 82.2202, -1.4859) -> (12.9687, 82.3788, -1.4859)
  line L3556 (12.9687, 82.3788, -1.4859) -> (13.1074, 82.5175, -1.4859)
  line L3557 (13.1074, 82.5175, -1.4859) -> (13.2661, 82.6328, -1.4859)
  line L3558 (13.2661, 82.6328, -1.4859) -> (13.4408, 82.7219, -1.4859)
  line L3559 (13.4408, 82.7219, -1.4859) -> (13.6274, 82.7825, -1.4859)
  line L3560 (13.6274, 82.7825, -1.4859) -> (13.8211, 82.8132, -1.4859)
  line L3561 (13.8211, 82.8132, -1.4859) -> (13.9192, 82.817, -1.4859)
  line L3562 (13.9192, 82.817, -1.4859) -> (14.4192, 82.817, -1.4859)
  line L3563 (14.4192, 82.817, -1.4859) -> (14.5173, 82.8132, -1.4859)
  line L3564 (22.1373, 82.8132, -1.4859) -> (22.331, 82.7825, -1.4859)
  line L3565 (22.331, 82.7825, -1.4859) -> (22.5175, 82.7219, -1.4859)
  line L3566 (22.5175, 82.7219, -1.4859) -> (22.6923, 82.6328, -1.4859)
  line L3567 (22.6923, 82.6328, -1.4859) -> (22.851, 82.5175, -1.4859)
  line L3568 (22.851, 82.5175, -1.4859) -> (22.9897, 82.3788, -1.4859)
  line L3569 (22.9897, 82.3788, -1.4859) -> (23.105, 82.2202, -1.4859)
  line L3570 (23.105, 82.2202, -1.4859) -> (23.194, 82.0454, -1.4859)
  line L3571 (23.194, 82.0454, -1.4859) -> (23.2546, 81.8588, -1.4859)
  line L3572 (23.2546, 81.8588, -1.4859) -> (23.2853, 81.6651, -1.4859)
  line L3573 (23.2853, 81.6651, -1.4859) -> (23.2853, 81.469, -1.4859)
  line L3574 (23.2853, 81.469, -1.4859) -> (23.2546, 81.2752, -1.4859)
  line L3575 (23.2546, 81.2752, -1.4859) -> (23.194, 81.0887, -1.4859)
  line L3576 (23.194, 81.0887, -1.4859) -> (23.105, 80.9139, -1.4859)
  line L3577 (23.105, 80.9139, -1.4859) -> (22.9897, 80.7552, -1.4859)
  line L3578 (22.9897, 80.7552, -1.4859) -> (22.851, 80.6165, -1.4859)
  line L3579 (22.851, 80.6165, -1.4859) -> (22.6923, 80.5012, -1.4859)
  line L3580 (22.6923, 80.5012, -1.4859) -> (22.5175, 80.4122, -1.4859)
  line L3581 (22.5175, 80.4122, -1.4859) -> (22.331, 80.3516, -1.4859)
  line L3582 (22.331, 80.3516, -1.4859) -> (22.1373, 80.3209, -1.4859)
  line L3583 (22.1373, 80.3209, -1.4859) -> (22.0392, 80.317, -1.4859)
  line L3584 (22.0392, 80.317, -1.4859) -> (21.5392, 80.317, -1.4859)
  line L3585 (21.5392, 80.317, -1.4859) -> (21.4411, 80.3209, -1.4859)
  line L3586 (21.4411, 80.3209, -1.4859) -> (21.2474, 80.3516, -1.4859)
  line L3587 (21.2474, 80.3516, -1.4859) -> (21.0608, 80.4122, -1.4859)
  line L3588 (21.0608, 80.4122, -1.4859) -> (20.8861, 80.5012, -1.4859)
  line L3589 (20.8861, 80.5012, -1.4859) -> (20.7274, 80.6165, -1.4859)
  line L3590 (20.7274, 80.6165, -1.4859) -> (20.5887, 80.7552, -1.4859)
  line L3591 (20.5887, 80.7552, -1.4859) -> (20.4734, 80.9139, -1.4859)
  line L3592 (20.4734, 80.9139, -1.4859) -> (20.3843, 81.0887, -1.4859)
  line L3593 (20.3843, 81.0887, -1.4859) -> (20.3237, 81.2752, -1.4859)
  line L3594 (20.3237, 81.2752, -1.4859) -> (20.293, 81.469, -1.4859)
  line L3595 (20.293, 81.469, -1.4859) -> (20.293, 81.6651, -1.4859)
  line L3596 (20.293, 81.6651, -1.4859) -> (20.3237, 81.8588, -1.4859)
  line L3597 (20.3237, 81.8588, -1.4859) -> (20.3843, 82.0454, -1.4859)
  line L3598 (20.3843, 82.0454, -1.4859) -> (20.4734, 82.2202, -1.4859)
  line L3599 (20.4734, 82.2202, -1.4859) -> (20.5887, 82.3788, -1.4859)
  line L3600 (20.5887, 82.3788, -1.4859) -> (20.7274, 82.5175, -1.4859)
  line L3601 (20.7274, 82.5175, -1.4859) -> (20.8861, 82.6328, -1.4859)
  line L3602 (20.8861, 82.6328, -1.4859) -> (21.0608, 82.7219, -1.4859)
  line L3603 (21.0608, 82.7219, -1.4859) -> (21.2474, 82.7825, -1.4859)
  line L3604 (21.2474, 82.7825, -1.4859) -> (21.4411, 82.8132, -1.4859)
  line L3605 (21.4411, 82.8132, -1.4859) -> (21.5392, 82.817, -1.4859)
  line L3606 (21.5392, 82.817, -1.4859) -> (22.0392, 82.817, -1.4859)
  line L3607 (22.0392, 82.817, -1.4859) -> (22.1373, 82.8132, -1.4859)
  line L3608 (49.4423, 82.8132, -1.4859) -> (49.636, 82.7825, -1.4859)
  line L3609 (49.636, 82.7825, -1.4859) -> (49.8225, 82.7219, -1.4859)
  line L3610 (49.8225, 82.7219, -1.4859) -> (49.9973, 82.6328, -1.4859)
  line L3611 (49.9973, 82.6328, -1.4859) -> (50.156, 82.5175, -1.4859)
  line L3612 (50.156, 82.5175, -1.4859) -> (50.2947, 82.3788, -1.4859)
  line L3613 (50.2947, 82.3788, -1.4859) -> (50.41, 82.2202, -1.4859)
  line L3614 (50.41, 82.2202, -1.4859) -> (50.499, 82.0454, -1.4859)
  line L3615 (50.499, 82.0454, -1.4859) -> (50.5596, 81.8588, -1.4859)
  line L3616 (50.5596, 81.8588, -1.4859) -> (50.5903, 81.6651, -1.4859)
  line L3617 (50.5903, 81.6651, -1.4859) -> (50.5903, 81.469, -1.4859)
  line L3618 (50.5903, 81.469, -1.4859) -> (50.5596, 81.2752, -1.4859)
  line L3619 (50.5596, 81.2752, -1.4859) -> (50.499, 81.0887, -1.4859)
  line L3620 (50.499, 81.0887, -1.4859) -> (50.41, 80.9139, -1.4859)
  line L3621 (50.41, 80.9139, -1.4859) -> (50.2947, 80.7552, -1.4859)
  line L3622 (50.2947, 80.7552, -1.4859) -> (50.156, 80.6165, -1.4859)
  line L3623 (50.156, 80.6165, -1.4859) -> (49.9973, 80.5012, -1.4859)
  line L3624 (49.9973, 80.5012, -1.4859) -> (49.8225, 80.4122, -1.4859)
  line L3625 (49.8225, 80.4122, -1.4859) -> (49.636, 80.3516, -1.4859)
  line L3626 (49.636, 80.3516, -1.4859) -> (49.4423, 80.3209, -1.4859)
  line L3627 (49.4423, 80.3209, -1.4859) -> (49.3442, 80.317, -1.4859)
  line L3628 (49.3442, 80.317, -1.4859) -> (48.8442, 80.317, -1.4859)
  line L3629 (48.8442, 80.317, -1.4859) -> (48.7461, 80.3209, -1.4859)
  line L3630 (48.7461, 80.3209, -1.4859) -> (48.5524, 80.3516, -1.4859)
  line L3631 (48.5524, 80.3516, -1.4859) -> (48.3658, 80.4122, -1.4859)
  line L3632 (48.3658, 80.4122, -1.4859) -> (48.1911, 80.5012, -1.4859)
  line L3633 (48.1911, 80.5012, -1.4859) -> (48.0324, 80.6165, -1.4859)
  line L3634 (48.0324, 80.6165, -1.4859) -> (47.8937, 80.7552, -1.4859)
  line L3635 (47.8937, 80.7552, -1.4859) -> (47.7784, 80.9139, -1.4859)
  line L3636 (47.7784, 80.9139, -1.4859) -> (47.6893, 81.0887, -1.4859)
  line L3637 (47.6893, 81.0887, -1.4859) -> (47.6287, 81.2752, -1.4859)
  line L3638 (47.6287, 81.2752, -1.4859) -> (47.598, 81.469, -1.4859)
  line L3639 (47.598, 81.469, -1.4859) -> (47.598, 81.6651, -1.4859)
  line L3640 (47.598, 81.6651, -1.4859) -> (47.6287, 81.8588, -1.4859)
  line L3641 (47.6287, 81.8588, -1.4859) -> (47.6893, 82.0454, -1.4859)
  line L3642 (47.6893, 82.0454, -1.4859) -> (47.7784, 82.2202, -1.4859)
  line L3643 (47.7784, 82.2202, -1.4859) -> (47.8937, 82.3788, -1.4859)
  line L3644 (47.8937, 82.3788, -1.4859) -> (48.0324, 82.5175, -1.4859)
  line L3645 (48.0324, 82.5175, -1.4859) -> (48.1911, 82.6328, -1.4859)
  line L3646 (48.1911, 82.6328, -1.4859) -> (48.3658, 82.7219, -1.4859)
  line L3647 (48.3658, 82.7219, -1.4859) -> (48.5524, 82.7825, -1.4859)
  line L3648 (48.5524, 82.7825, -1.4859) -> (48.7461, 82.8132, -1.4859)
  line L3649 (48.7461, 82.8132, -1.4859) -> (48.8442, 82.817, -1.4859)
  line L3650 (48.8442, 82.817, -1.4859) -> (49.3442, 82.817, -1.4859)
  line L3651 (49.3442, 82.817, -1.4859) -> (49.4423, 82.8132, -1.4859)
  line L3652 (57.0623, 82.8132, -1.4859) -> (57.256, 82.7825, -1.4859)
  line L3653 (57.256, 82.7825, -1.4859) -> (57.4425, 82.7219, -1.4859)
  line L3654 (57.4425, 82.7219, -1.4859) -> (57.6173, 82.6328, -1.4859)
  line L3655 (57.6173, 82.6328, -1.4859) -> (57.776, 82.5175, -1.4859)
  line L3656 (57.776, 82.5175, -1.4859) -> (57.9147, 82.3788, -1.4859)
  line L3657 (57.9147, 82.3788, -1.4859) -> (58.03, 82.2202, -1.4859)
  line L3658 (58.03, 82.2202, -1.4859) -> (58.119, 82.0454, -1.4859)
  line L3659 (58.119, 82.0454, -1.4859) -> (58.1796, 81.8588, -1.4859)
  line L3660 (58.1796, 81.8588, -1.4859) -> (58.2103, 81.6651, -1.4859)
  line L3661 (58.2103, 81.6651, -1.4859) -> (58.2103, 81.469, -1.4859)
  line L3662 (58.2103, 81.469, -1.4859) -> (58.1796, 81.2752, -1.4859)
  line L3663 (58.1796, 81.2752, -1.4859) -> (58.119, 81.0887, -1.4859)
  line L3664 (58.119, 81.0887, -1.4859) -> (58.03, 80.9139, -1.4859)
  line L3665 (58.03, 80.9139, -1.4859) -> (57.9147, 80.7552, -1.4859)
  line L3666 (57.9147, 80.7552, -1.4859) -> (57.776, 80.6165, -1.4859)
  line L3667 (57.776, 80.6165, -1.4859) -> (57.6173, 80.5012, -1.4859)
  line L3668 (57.6173, 80.5012, -1.4859) -> (57.4425, 80.4122, -1.4859)
  line L3669 (57.4425, 80.4122, -1.4859) -> (57.256, 80.3516, -1.4859)
  line L3670 (57.256, 80.3516, -1.4859) -> (57.0623, 80.3209, -1.4859)
  line L3671 (57.0623, 80.3209, -1.4859) -> (56.9642, 80.317, -1.4859)
  line L3672 (56.9642, 80.317, -1.4859) -> (56.4642, 80.317, -1.4859)
  line L3673 (56.4642, 80.317, -1.4859) -> (56.3661, 80.3209, -1.4859)
  line L3674 (56.3661, 80.3209, -1.4859) -> (56.1724, 80.3516, -1.4859)
  line L3675 (56.1724, 80.3516, -1.4859) -> (55.9858, 80.4122, -1.4859)
  line L3676 (55.9858, 80.4122, -1.4859) -> (55.8111, 80.5012, -1.4859)
  line L3677 (55.8111, 80.5012, -1.4859) -> (55.6524, 80.6165, -1.4859)
  line L3678 (55.6524, 80.6165, -1.4859) -> (55.5137, 80.7552, -1.4859)
  line L3679 (55.5137, 80.7552, -1.4859) -> (55.3984, 80.9139, -1.4859)
  line L3680 (55.3984, 80.9139, -1.4859) -> (55.3093, 81.0887, -1.4859)
  line L3681 (55.3093, 81.0887, -1.4859) -> (55.2487, 81.2752, -1.4859)
  line L3682 (55.2487, 81.2752, -1.4859) -> (55.218, 81.469, -1.4859)
  line L3683 (55.218, 81.469, -1.4859) -> (55.218, 81.6651, -1.4859)
  line L3684 (55.218, 81.6651, -1.4859) -> (55.2487, 81.8588, -1.4859)
  line L3685 (55.2487, 81.8588, -1.4859) -> (55.3093, 82.0454, -1.4859)
  line L3686 (55.3093, 82.0454, -1.4859) -> (55.3984, 82.2202, -1.4859)
  line L3687 (55.3984, 82.2202, -1.4859) -> (55.5137, 82.3788, -1.4859)
  line L3688 (55.5137, 82.3788, -1.4859) -> (55.6524, 82.5175, -1.4859)
  line L3689 (55.6524, 82.5175, -1.4859) -> (55.8111, 82.6328, -1.4859)
  line L3690 (55.8111, 82.6328, -1.4859) -> (55.9858, 82.7219, -1.4859)
  line L3691 (55.9858, 82.7219, -1.4859) -> (56.1724, 82.7825, -1.4859)
  line L3692 (56.1724, 82.7825, -1.4859) -> (56.3661, 82.8132, -1.4859)
  line L3693 (56.3661, 82.8132, -1.4859) -> (56.4642, 82.817, -1.4859)
  line L3694 (56.4642, 82.817, -1.4859) -> (56.9642, 82.817, -1.4859)
  line L3695 (56.9642, 82.817, -1.4859) -> (57.0623, 82.8132, -1.4859)
  line L3696 (84.3673, 82.8132, -1.4859) -> (84.561, 82.7825, -1.4859)
  line L3697 (84.561, 82.7825, -1.4859) -> (84.7475, 82.7219, -1.4859)
  line L3698 (84.7475, 82.7219, -1.4859) -> (84.9223, 82.6328, -1.4859)
  line L3699 (84.9223, 82.6328, -1.4859) -> (85.081, 82.5175, -1.4859)
  line L3700 (85.081, 82.5175, -1.4859) -> (85.2197, 82.3788, -1.4859)
  line L3701 (85.2197, 82.3788, -1.4859) -> (85.335, 82.2202, -1.4859)
  line L3702 (85.335, 82.2202, -1.4859) -> (85.424, 82.0454, -1.4859)
  line L3703 (85.424, 82.0454, -1.4859) -> (85.4846, 81.8588, -1.4859)
  line L3704 (85.4846, 81.8588, -1.4859) -> (85.5153, 81.6651, -1.4859)
  line L3705 (85.5153, 81.6651, -1.4859) -> (85.5153, 81.469, -1.4859)
  line L3706 (85.5153, 81.469, -1.4859) -> (85.4846, 81.2752, -1.4859)
  line L3707 (85.4846, 81.2752, -1.4859) -> (85.424, 81.0887, -1.4859)
  line L3708 (85.424, 81.0887, -1.4859) -> (85.335, 80.9139, -1.4859)
  line L3709 (85.335, 80.9139, -1.4859) -> (85.2197, 80.7552, -1.4859)
  line L3710 (85.2197, 80.7552, -1.4859) -> (85.081, 80.6165, -1.4859)
  line L3711 (85.081, 80.6165, -1.4859) -> (84.9223, 80.5012, -1.4859)
  line L3712 (84.9223, 80.5012, -1.4859) -> (84.7475, 80.4122, -1.4859)
  line L3713 (84.7475, 80.4122, -1.4859) -> (84.561, 80.3516, -1.4859)
  line L3714 (84.561, 80.3516, -1.4859) -> (84.3673, 80.3209, -1.4859)
  line L3715 (84.3673, 80.3209, -1.4859) -> (84.2692, 80.317, -1.4859)
  line L3716 (84.2692, 80.317, -1.4859) -> (83.7692, 80.317, -1.4859)
  line L3717 (83.7692, 80.317, -1.4859) -> (83.6711, 80.3209, -1.4859)
  line L3718 (83.6711, 80.3209, -1.4859) -> (83.4774, 80.3516, -1.4859)
  line L3719 (83.4774, 80.3516, -1.4859) -> (83.2908, 80.4122, -1.4859)
  line L3720 (83.2908, 80.4122, -1.4859) -> (83.1161, 80.5012, -1.4859)
  line L3721 (83.1161, 80.5012, -1.4859) -> (82.9574, 80.6165, -1.4859)
  line L3722 (82.9574, 80.6165, -1.4859) -> (82.8187, 80.7552, -1.4859)
  line L3723 (82.8187, 80.7552, -1.4859) -> (82.7034, 80.9139, -1.4859)
  line L3724 (82.7034, 80.9139, -1.4859) -> (82.6143, 81.0887, -1.4859)
  line L3725 (82.6143, 81.0887, -1.4859) -> (82.5537, 81.2752, -1.4859)
  line L3726 (82.5537, 81.2752, -1.4859) -> (82.523, 81.469, -1.4859)
  line L3727 (82.523, 81.469, -1.4859) -> (82.523, 81.6651, -1.4859)
  line L3728 (82.523, 81.6651, -1.4859) -> (82.5537, 81.8588, -1.4859)
  line L3729 (82.5537, 81.8588, -1.4859) -> (82.6143, 82.0454, -1.4859)
  line L3730 (82.6143, 82.0454, -1.4859) -> (82.7034, 82.2202, -1.4859)
  line L3731 (82.7034, 82.2202, -1.4859) -> (82.8187, 82.3788, -1.4859)
  line L3732 (82.8187, 82.3788, -1.4859) -> (82.9574, 82.5175, -1.4859)
  line L3733 (82.9574, 82.5175, -1.4859) -> (83.1161, 82.6328, -1.4859)
  line L3734 (83.1161, 82.6328, -1.4859) -> (83.2908, 82.7219, -1.4859)
  line L3735 (83.2908, 82.7219, -1.4859) -> (83.4774, 82.7825, -1.4859)
  line L3736 (83.4774, 82.7825, -1.4859) -> (83.6711, 82.8132, -1.4859)
  line L3737 (83.6711, 82.8132, -1.4859) -> (83.7692, 82.817, -1.4859)
  line L3738 (83.7692, 82.817, -1.4859) -> (84.2692, 82.817, -1.4859)
  line L3739 (84.2692, 82.817, -1.4859) -> (84.3673, 82.8132, -1.4859)
  line L3740 (91.9873, 82.8132, -1.4859) -> (92.181, 82.7825, -1.4859)
  line L3741 (92.181, 82.7825, -1.4859) -> (92.3675, 82.7219, -1.4859)
  line L3742 (92.3675, 82.7219, -1.4859) -> (92.5423, 82.6328, -1.4859)
  line L3743 (92.5423, 82.6328, -1.4859) -> (92.701, 82.5175, -1.4859)
  line L3744 (92.701, 82.5175, -1.4859) -> (92.8397, 82.3788, -1.4859)
  line L3745 (92.8397, 82.3788, -1.4859) -> (92.955, 82.2202, -1.4859)
  line L3746 (92.955, 82.2202, -1.4859) -> (93.044, 82.0454, -1.4859)
  line L3747 (93.044, 82.0454, -1.4859) -> (93.1046, 81.8588, -1.4859)
  line L3748 (93.1046, 81.8588, -1.4859) -> (93.1353, 81.6651, -1.4859)
  line L3749 (93.1353, 81.6651, -1.4859) -> (93.1353, 81.469, -1.4859)
  line L3750 (93.1353, 81.469, -1.4859) -> (93.1046, 81.2752, -1.4859)
  line L3751 (93.1046, 81.2752, -1.4859) -> (93.044, 81.0887, -1.4859)
  line L3752 (93.044, 81.0887, -1.4859) -> (92.955, 80.9139, -1.4859)
  line L3753 (92.955, 80.9139, -1.4859) -> (92.8397, 80.7552, -1.4859)
  line L3754 (92.8397, 80.7552, -1.4859) -> (92.701, 80.6165, -1.4859)
  line L3755 (92.701, 80.6165, -1.4859) -> (92.5423, 80.5012, -1.4859)